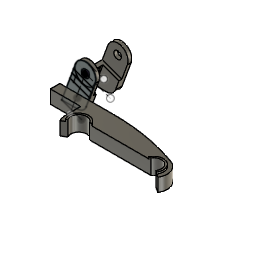
hot-end-mount-v13 (Autodesk Fusion 360 design; units mm, degrees)
Autodesk Fusion 360 part; units mm, degrees
sketch "Sketch1" plane through (0, 0, 0) normal (0, 0, 1) x (1, 0, 0) in component "bracket"
  circle A0 centre (26.9017, -0.0451) radius 4.2
  circle A1 centre (66.4017, -0.0451) radius 4.2
  line L0 (-74.3453, -0.0451) -> (146.9069, -0.0451) construction
  circle A2 centre (26.9017, -0.0451) radius 2.5 construction
  circle A3 centre (66.4017, -0.0451) radius 2.5 construction
  line L1 (29.4017, -0.0451) -> (29.4017, 11) construction
  line L2 (63.9017, -0.0451) -> (63.9017, 11) construction
  line L3 (0, 4.1549) -> (68, 4.1549) construction
  line L4 (-2.9065, 2.1549) -> (79.191, 2.1549) construction
  line L5 (30.4794, 2.1549) -> (62.824, 2.1549)
  circle A4 centre (26.9017, -0.0451) radius 5.2
  circle A5 centre (66.4017, -0.0451) radius 5.2
  line L6 (30.4794, 2.1549) -> (26.9017, -0.0451)
  line L7 (26.9017, -0.0451) -> (15.8278, -6.8546)
  line L8 (62.824, 2.1549) -> (66.4017, -0.0451)
  line L9 (66.4017, -0.0451) -> (77.4756, -6.8546)
  line L10 (77.4756, -6.8546) -> (15.8278, -6.8546)
  line L11 (19.7017, 13.1549) -> (73.6017, 13.1549)
  line L12 (73.6017, 13.1549) -> (73.6017, -5.3442)
  line L13 (73.6017, -5.3442) -> (19.7017, -5.3442)
  line L14 (19.7017, -5.3442) -> (19.7017, 13.1549)
  line L15 (0, 5.1549) -> (69, 5.1549) construction
  circle A6 centre (26.9017, -0.0451) radius 7.2
  circle A7 centre (66.4017, -0.0451) radius 7.2
  line L16 (19.7017, -0.0451) -> (19.7017, 11.5179) construction
  line L17 (73.6017, -0.0451) -> (73.6017, 8) construction
  line L18 (19.7017, 13.1549) -> (32, 13.1549)
  arc A8 (68.8081, 6.7409) -> (32, 13.1549) centre (32, -95.6669) ccw
  line L19 (19.7017, 13.1549) -> (3.7017, 13.1549)
  line L20 (3.7017, 13.1549) -> (3.7017, 8.1549)
  line L21 (3.7017, 8.1549) -> (19.7017, 8.1549)
  line L22 (19.7017, 8.1549) -> (19.7017, 13.1549)
  dimension "d5" = 8.4
  dimension "d6" = 8.4
  dimension "d8" = 5
  dimension "d9" = 5
  dimension "d11" = 34.5
  dimension "d12" = 2
  dimension "d13" = 1
  dimension "d14" = 1
  dimension "d18" = 13
  dimension "d19" = 13
  dimension "d20" = 8
  dimension "d22" = 3
  dimension "d23" = 3
  dimension "d26" = 5
  dimension "d27" = 16
  constraint horizontal L0
  constraint coincident A0.centre L0
  constraint coincident A1.centre L0
  constraint concentric A0 A2
  constraint concentric A1 A3
  constraint coincident L0 L1.start
  constraint perpendicular L0 L1
  constraint tangent A2 L1
  constraint coincident L0 L2.start
  constraint perpendicular L0 L2
  constraint tangent A3 L2
  constraint perpendicular L2 L3
  constraint tangent A1 L3
  constraint parallel L3 L4
  constraint coincident A0 L5.start
  constraint coincident L4 L5.start
  constraint coincident A1 L5.end
  constraint coincident L4 L5.end
  constraint coincident A0.centre A2.centre
  constraint parallel L6 L7
  constraint coincident A1.centre A3.centre
  constraint parallel L8 L9
  constraint horizontal L11
  constraint vertical L12
  constraint horizontal L13
  constraint vertical L14
  constraint perpendicular L2 L15
  constraint tangent A4 L15
  constraint coincident L0 L16.start
  constraint perpendicular L4 L16
  constraint coincident L0 L17.start
  constraint perpendicular L0 L17
  constraint tangent A7 L17
  constraint tangent A6 L16
  constraint collinear L14 L16
  constraint collinear L12 L17
  constraint coincident L11 L18.end
  constraint coincident A7 A8.start
  constraint tangent L18 A8
  constraint horizontal L19
  constraint vertical L20
  constraint horizontal L21
  constraint vertical L22
  measures "d5" diameter of A1
  measures "d6" diameter of A0
  measures "d8" diameter of A3
  measures "d9" diameter of A2
  measures "d11" distance of L1 L2
  measures "d12" distance of L3 L4
  measures "d18" distance of A0.centre L7.end
  measures "d19" distance of A1.centre L9.end
  measures "d20" distance of L11 L15
  measures "d26" distance of L19.end L20.end
  measures "d27" distance of L11.start L19.end
extrude "Extrude1" add sketch "Sketch1" along normal blind 7 contours A0 L5 A4 L7 | L5 A4 L7 A6 | L5 L11 L14 A6 A7 L18 A8 L22 | L5 A5 L9 A7 | A1 L5 A5 L9 | L14 L19 L20 L21 L22 picked at (31.1101, 2.3785) picked at (62.1879, 2.3703) makes body 1 in component "bracket"
extrude "Extrude2" add sketch "Sketch1" along normal blind 1 from surface at 7 contours A0 L5 A4 L7 | A1 L5 A5 L9 picked at (31.1101, 2.3785) picked at (62.1879, 2.3703) bodies 1 in component "bracket"
sketch "main" plane through (0, 0, 0) normal (0, 1, 0) x (1, 0, 0) in component "chain"
  circle A0 centre (0, 0) radius 2
  circle A1 centre (0, 0) radius 5.5
  line L0 (0, 0) -> (0, -14) construction
  line L1 (0, 0) -> (24, 0) construction
  line L2 (13.9953, -5.5) -> (3, -5.5)
  line L3 (3, -5.5) -> (3, 5.5)
  line L4 (3, 5.5) -> (21.5, 5.5)
  line L5 (21.5, 5.5) -> (21.5, -5.5)
  line L6 (21.5, 0) -> (3, 0) construction
  line L7 (3, -5.5) -> (0, -5.5)
  line L8 (3, 5.5) -> (0, 5.5)
  line L9 (-5.5, 0) -> (-5.5, -8.3145) construction
  line L10 (21.5, 5.5) -> (18.6938, -2.2101)
  arc A2 (13.9953, -5.5) -> (18.6938, -2.2101) centre (13.9953, -0.5) ccw
  line L11 (5.5, 5.5) -> (5.5, -5.5) construction
  line L12 (5.5, 3.4) -> (8.6, 3.4)
  line L13 (8.6, 3.4) -> (8.6, -5.5)
  line L14 (8.6, -5.5) -> (5.5, -5.5)
  line L15 (5.5, -5.5) -> (5.5, 3.4)
  line L16 (5.5, 3.4) -> (4.3232, 3.4)
  line L17 (5.5, 3.4) -> (5.5, 5.5)
  line L18 (8.6, 3.4) -> (8.6, 5.5)
  dimension "d56" = 4
  dimension "d58" = 3
  dimension "d59" = 11
  dimension "d60" = 18.5
  dimension "d61" = 70
  dimension "d62" = 5
  dimension "d111" = 11
  dimension "d112" = 2.1
  dimension "d113" = 3.1
  constraint coincident A0.centre A1.centre
  constraint vertical L0
  constraint perpendicular L0 L1
  constraint horizontal L2
  constraint vertical L3
  constraint horizontal L4
  constraint vertical L5
  constraint midpoint L5 L6.start
  constraint midpoint L3 L6.end
  constraint collinear L1 L6
  constraint coincident A1 L7.end
  constraint coincident L0 L7.end
  constraint coincident A1 L8.end
  constraint tangent A1 L8
  constraint coincident A1 L9.start
  constraint tangent A1 L9
  constraint parallel L3 L9
  constraint tangent L2 A2
  constraint tangent L10 A2
  constraint concentric A0 A1
  constraint coincident L4 L11.start
  constraint coincident L2 L11.end
  constraint perpendicular L2 L11
  constraint tangent A1 L11
  constraint horizontal L12
  constraint vertical L13
  constraint horizontal L14
  constraint vertical L15
  constraint coincident L2 L13.end
  constraint coincident L11 L12.start
  constraint coincident A1 L16.end
  constraint perpendicular L11 L16
  constraint coincident L4 L18.end
  constraint perpendicular L4 L18
  measures "d56" diameter of A0
  measures "d58" distance of L0 L3
  measures "d59" distance of L5.end L4.end
  measures "d60" distance of L5.end L2.end
  measures "d61" angle of L4 L10
  measures "d62" radius of A2
  measures "d111" diameter of A1
  measures "d112" distance of L4 L12
  measures "d113" distance of L12.start L12.end
extrude "Extrude1'" add sketch "main" along normal blind 19 separate body makes body 2 in component "chain"
sketch "primary_hole" plane through (0, 0, 0) normal (1, 0, 0) x (0, 1, 0) in component "chain"
  line L0 (15.5, 8.5) -> (3.5, 8.5)
  line L1 (3.5, 8.5) -> (3.5, -3.5)
  line L2 (3.5, -3.5) -> (15.5, -3.5)
  line L3 (15.5, -3.5) -> (15.5, 8.5)
  line L4 (19, -5.5) -> (19, 5.5)
  line L5 (0, -5.5) -> (19, -5.5)
  line L6 (0, -5.5) -> (0, 5.5)
  dimension "d65" = 3.5
  dimension "d66" = 2
  dimension "d67" = 3.5
  dimension "d69" = 12
  constraint horizontal L0
  constraint vertical L1
  constraint horizontal L2
  constraint vertical L3
  measures "d65" distance of L3 L4
  measures "d66" distance of L2 L5
  measures "d67" distance of L1 L6
  measures "d69" distance of L0 L2
extrude "Extrude2'" cut sketch "primary_hole" along normal through all and the other way through all bodies 2 in component "chain"
extrude "Extrude3" cut sketch "main" along normal mid plane 3 from surface at 3.5 contours A1 L3 | A1 L3 L7 | A1 L3 | A1 L3 L8 bodies 2 in component "chain"
extrude "Extrude4" cut sketch "main" along normal blind 13.5 from surface at 3.5 contours A1 L3 | A1 L3 L7 | A1 L3 | A1 L3 L8 bodies 2 in component "chain"
sketch "tie wrap mount" plane through (0, 0, 0) normal (0, 0, 1) x (1, 0, 0) in component "chain"
  line L0 (9.5, 14.5) -> (12.5, 14.5)
  line L1 (12.5, 14.5) -> (12.5, 12.5)
  line L2 (12.5, 12.5) -> (9.5, 12.5)
  line L3 (9.5, 12.5) -> (9.5, 14.5)
  line L4 (16.5, 14.5) -> (19.5, 14.5)
  line L5 (19.5, 14.5) -> (19.5, 12.5)
  line L6 (19.5, 12.5) -> (16.5, 12.5)
  line L7 (16.5, 12.5) -> (16.5, 14.5)
  line L8 (9.5, 6.5) -> (12.5, 6.5)
  line L9 (12.5, 6.5) -> (12.5, 4.5)
  line L10 (12.5, 4.5) -> (9.5, 4.5)
  line L11 (9.5, 4.5) -> (9.5, 6.5)
  line L12 (16.5, 6.5) -> (19.5, 6.5)
  line L13 (19.5, 6.5) -> (19.5, 4.5)
  line L14 (19.5, 4.5) -> (16.5, 4.5)
  line L15 (16.5, 4.5) -> (16.5, 6.5)
  line L16 (13.9953, 3.5) -> (18.6938, 3.5)
  line L17 (13.9953, 3.5) -> (3, 3.5)
  line L18 (3, 15.5) -> (13.9953, 15.5)
  line L19 (18.6938, 15.5) -> (13.9953, 15.5)
  line L20 (21.5, 0) -> (21.5, 19)
  dimension "d90" = 2
  dimension "d91" = 3
  dimension "d92" = 3
  dimension "d93" = 2
  dimension "d94" = 3
  dimension "d95" = 2
  dimension "d96" = 2
  dimension "d97" = 3
  dimension "d98" = 1
  dimension "d99" = 1
  dimension "d100" = 1
  dimension "d101" = 1
  dimension "d102" = 4
  dimension "d103" = 4
  dimension "d104" = 2
  dimension "d105" = 2
  constraint horizontal L0
  constraint vertical L1
  constraint horizontal L2
  constraint vertical L3
  constraint horizontal L4
  constraint vertical L5
  constraint horizontal L6
  constraint vertical L7
  constraint horizontal L8
  constraint vertical L9
  constraint horizontal L10
  constraint vertical L11
  constraint horizontal L12
  constraint vertical L13
  constraint horizontal L14
  constraint vertical L15
  measures "d90" distance of L0.start L2.end
  measures "d91" distance of L0.start L0.end
  measures "d92" distance of L4.start L4.end
  measures "d93" distance of L4.start L6.end
  measures "d94" distance of L13.end L14.end
  measures "d95" distance of L12.start L14.end
  measures "d96" distance of L8.start L10.end
  measures "d97" distance of L9.end L10.end
  measures "d98" distance of L14 L16
  measures "d99" distance of L10 L17
  measures "d100" distance of L0 L18
  measures "d101" distance of L4 L19
  measures "d102" distance of L1 L7
  measures "d103" distance of L9 L15
  measures "d104" distance of L5 L20
  measures "d105" distance of L13 L20
extrude "Extrude5" cut sketch "tie wrap mount" along normal through all and the other way through all bodies 2 in component "chain"
combine "Combine1" operation add target body 2 tool bodies 1 body 1 seen with x (-0.34202, 0, 0.939693) y (0, 1, 0) z (-0.939693, 0, -0.34202) at (23.1081, -13.1549, -9.9181) in component "chain"
extrude "Extrude8" cut sketch "main" along normal blind 15 from surface at 2 contours A1 L2 L3 L15 | L2 L12 L13 L14 L15 | A1 L15 L16 bodies 2 in component "chain"
extrude "Extrude9" cut sketch "main" along normal blind 15 from surface at 2 contours A1 L3 L4 L16 L17 bodies 2 in component "chain"
extrude "Extrude10" cut sketch "main" along normal blind 15 from surface at 2 contours L4 L12 L17 L18 bodies 2 in component "chain"
component "bracket" placed x (1, 0, 0) y (0, 1, 0) z (0, 0, 1) at (0, 0, 0)
component "chain" placed x (-0.34202, 0, -0.939693) y (0, 1, 0) z (0.939693, 0, -0.34202) at (17.2234, 13.1549, 18.3223)
equation "spacer_diameter = 8.4 mm"
equation "drop = 2 mm"
equation "thickness = 7 mm"
equation "offset = 1 mm"
equation "d5 = spacer_diameter"
equation "d6 = spacer_diameter"
equation "hole = 5 mm"
equation "d8 = hole"
equation "d9 = hole"
equation "holes_gap = 34.5 mm"
equation "d11 = holes_gap"
equation "d12 = drop"
equation "d13 = offset"
equation "d14 = offset"
equation "d20 = upper_length"
equation "upper_length = 8 mm"
equation "d22 = offset + 2 mm"
equation "d23 = offset + 2 mm"
equation "extra_width = 16 mm"
equation "extra_height = 5 mm"
equation "d26 = extra_height"
equation "d27 = extra_width"
equation "d28 = thickness"
equation "d30 = thickness"
equation "d31 = offset"
equation "chain_thickness = 3.5 mm"
equation "chain_hole = 3 mm"
equation "chain_height = 12 mm"
equation "chain_hole_offset = 4 mm"
equation "chain_length = 27 mm"
equation "chain_width = 19 mm"
equation "chain_hole_reduction = 2 mm"
equation "d56 = chain_hole + tolerance"
equation "d59 = chain_hole + 2 * chain_hole_offset"
equation "d60 = chain_length - chain_hole_offset - ( chain_hole / 2 ) - 3 mm"
equation "d63 = chain_width"
equation "d65 = chain_thickness"
equation "d66 = chain_thickness - 1.5 mm"
equation "d67 = chain_thickness"
equation "d69 = chain_height"
equation "d70 = chain_thickness"
equation "d71 = chain_thickness - 2 mm"
equation "d73 = chain_thickness"
equation "d74 = chain_width - 5.5 mm"
equation "d92 = d91"
equation "d93 = d90"
equation "d94 = d91"
equation "d95 = d90"
equation "d96 = d90"
equation "d97 = d91"
equation "d98 = d100"
equation "d99 = d100"
equation "d101 = d100"
equation "d103 = d102"
equation "d105 = d104"
equation "d112 = chain_clearance_offset"
equation "d113 = chain_clearance_w"
equation "chain_clearance_offset = 2.1 mm"
equation "chain_clearance_w = 3.1 mm"
equation "d121 = chain_hole_reduction"
equation "d122 = chain_width - 4 mm"
equation "d124 = chain_hole_reduction"
equation "d125 = chain_width - 4 mm"
equation "d127 = chain_hole_reduction"
equation "d128 = chain_width - 4 mm"
equation "tolerance = 1 mm"
